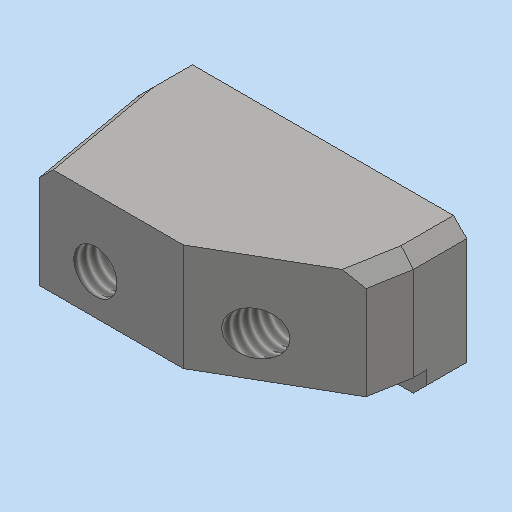
# Autodesk Inventor part: MM0948AN100_G01_124
Saved by Autodesk Inventor 2023.3 (Build 273359000, 359)
## iProperties
Created: 2023-03-23
Part Number: MM0948AN100_G01_124
Material: 1.2842 90MnCrV8
Description: =<RBPARTNOTITLE2>
Document SubType Name: Modeling
Designer: grc1gar
Mass: 14.7914 g
Surface Area: 13.3039 cm^2
Volume: 1.88426 cm^3
Density: 7.85 g/cm^3
Appearance: Stahl - normal AnP
AnP_Kategorie: 1
AnP_Material: =<Material>
MaxAbmaße: 10 x 14 x 21,5 (FM)
AnP_TemplVers: 20200821
RBDOCUMENTTYPE: DRF
RBDOCUMENTVERSION: 00
RBDRAWINGMAINSCALE: 1:1
RBDRAWINGMISSINGSPEC: --
RBDRAWINGVOLUME: --
RBDSV1: 0850
RBGBEDGESIN1: +0,5
RBGBEDGESIN2: +0,2
RBGBEDGESOUT1: -0,3
RBGBEDGESOUT2: -0,1
RBMATERIAL: =<Material>
RBMATMEETS: --
RBMATNO: =<Part Number>
RBPARTMADEOF: 10 x 14 x 21,5 (FM)
RBPARTNO: SIEHE MNR
RBPARTNOTITLE1: manufactured part
RBPARTNOTITLE2: Anfertigungsteil
RBPARTSAFETYINDICATOR: --
RBSURFACE: plasma nitrided 550 HV, Nht 0,2 + 0,1
RBSURFACE2: plasmanitriert 550 HV, Nht 0,2 + 0,1
RBZEDGESNORM: ISO13715:2002-06
RBZGENDIMCLASS: m
RBZGENDIMNORM: ISO 2768-1:1989-11
RBZGENGEOCLASS: H
RBZGENGEONORM: ISO 2768-2:1989-11
RBZSURFACENORM: ISO13D2:2002-02
RBZTOLERANCENORM: ISO 14405-1:2010-12
AnP_Kommentar_aktuell: =<Comments>
AnP_Material_aktuell: =<Material>
Author: FH/Wi
Keywords: =<RBPARTMADEOF>
Comments: =<RBSURFACE2>
Revision Number: 01
Autodesk Inventor part; units mm, degrees
ref_plane "YZ Plane" through (0, 0, 0) normal (1, 0, 0) x (0, 1, 0)
ref_plane "XZ Plane" through (0, 0, 0) normal (0, 1, 0) x (-1, 0, 0)
ref_plane "XY Plane" through (0, 0, 0) normal (0, 0, 1) x (1, 0, 0)
sketch "Skizze1" plane through (0, 0, 0) normal (0, 0, 1) x (1, 0, 0)
  line L0 (10.75, 0) -> (10.75, -4)
  line L1 (1.5608, -12) -> (-9.1631, -12)
  line L2 (-10.75, -3) -> (-10.75, 0)
  line L3 (-10.75, 0) -> (10.75, 0)
  line L4 (-10.75, -3) -> (-9.1631, -12)
  line L5 (1.5608, -12) -> (10.221, -7)
  line L6 (10.75, -4) -> (10.221, -7)
  line L7 (0, 2.4) -> (0, -14.4) projected
  point P0 (0, 0)
  point P1 (0, 0)
  dimension "d8" = 21.5
  dimension "d23" = 12
  dimension "d24" = 170
  dimension "d25" = 120
  dimension "d26" = 3
  dimension "d28" = 7
  dimension "d49" = 4
  dimension "d50" = 170
  constraints: 14 end point, 2 perpendicular, 1 coincident, 1 horizontal, 1 midpoint
  measures "d8" distance between parallel lines of L0 L2
  measures "d23" distance between parallel lines of L1 L3
  measures "d24" angle of L2 L4
  measures "d25" angle of L0 L5
  measures "d26" distance from line of L2.start L3
  measures "d28" distance from line of L5.end L3
  measures "d49" distance from line of L3 L0.end
  measures "d50" angle of L0 L6
extrude "Extrusion1" add sketch "Skizze1" along normal mid plane 10
sketch "Skizze4" plane through (-10.75, 0, -5) normal (0, 1, 0) x (1, 0, 0)
  line L0 (5.75, -2) -> (15.75, -2)
  line L1 (15.75, -8) -> (5.75, -8)
  line L2 (-4.3, -5) -> (25.8, -5) construction
  line L3 (0, 0) -> (0, -10) projected
  line L4 (21.5, -10) -> (0, -10) projected
  line L5 (21.5, 0) -> (21.5, -10) projected
  line L6 (0, 0) -> (21.5, 0) projected
  line L7 (0, 0) -> (0, -10) projected
  line L8 (21.5, 0) -> (21.5, -10) projected
  arc A0 (15.75, -8) -> (15.75, -2) centre (15.75, -5) ccw
  arc A1 (5.75, -2) -> (5.75, -8) centre (5.75, -5) ccw
  line L9 (10.75, 2) -> (10.75, -12) projected
  point P0 (10.75, -5)
  dimension "d29" = 6
  dimension "d45" = 10
  constraints: 4 end point, 4 point on circle, 2 centre point, 2 point on line, 2 tangent, 1 horizontal, 1 parallel, 2 other
  measures "d29" distance between parallel lines of L1 L0
  measures "d45" distance of A0.centre A1.centre
extrude "Extrusion4" add sketch "Skizze4" along normal blind 2 contours L0 L9 L1 A1 | L0 A0 L1 L9
sketch "Skizze5" plane through (-10.75, 2, -5) normal (0, 1, 0) x (1, 0, 0)
  line L0 (25.8, -5) -> (-4.3, -5) projected
  line L1 (21.5, 0) -> (21.5, -10) projected
  line L2 (0, 0) -> (0, -10) projected
  line L3 (0, 0) -> (0, -10) projected
  line L4 (10.75, 2) -> (10.75, -12) projected
  line L5 (21.5, 0) -> (21.5, -10) projected
  point P0 (10.75, -5)
  point P1 (5.75, -5)
  point P2 (15.75, -5)
  dimension "d32" = 10
  constraints: 1 horizontal alignment, 1 point on line, 1 symmetric about line
  measures "d32" distance of point (5.75, -5) point (15.75, -5)
hole "Bohrung1" at (-5, 2, 0) at (5, 2, 0) direction (0, -1, 0) diameter 3.242 end through all thread size "M4x0.7" designation "M4" class "6H" standard "ISO Metric profile"
sketch "Skizze6" plane through (0, 0, -5) normal (0, 0, -1) x (-1, 0, 0)
  line L0 (-10.75, -3) -> (10.75, -3)
  line L1 (10.75, -3) -> (10.75, -12)
  line L2 (10.75, -12) -> (-10.75, -12)
  line L3 (-10.75, -12) -> (-10.75, -3)
  line L4 (6.621, -12) -> (3.379, -12) projected
  line L5 (9.1631, -12) -> (-1.5608, -12) projected
  line L6 (-1.5608, -12) -> (9.1631, -12) projected
  line L7 (-10.75, -4) -> (-10.75, 0) projected
  line L8 (-10.75, 0) -> (-10.75, -4) projected
  line L9 (10.75, 0) -> (10.75, -3) projected
  line L10 (10.75, -3) -> (10.75, 0) projected
  point P0 (0, 0)
  point P1 (-3.379, -12)
  point P2 (-6.621, -12)
  dimension "d41" = 9
  constraints: 8 end point, 3 collinear, 1 horizontal, 1 parallel, 1 perpendicular
  measures "d41" distance between parallel lines of L2 L0
extrude "Extrusion5" cut sketch "Skizze6" against normal blind 2
chamfer "Fase1" distance 1 angle 45 6 edges at (10.75, -2, 5) (10.75, -1.5, -5) (-10.75, -1.5, 5) (-9.9565, -7.5, 5) (-10.75, -1.5, -5) (10.4855, -5.5, 5)
